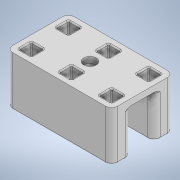
# Autodesk Inventor part: suport_culisant_new_2
Saved by Autodesk Inventor 2022.6 (Build 266554000, 554)
## iProperties
Created: 2026-01-10
Part Number: suport_culisant_new_2
Material: Generic
Document SubType Name: Modeling
Designer: Dragos Macovei
Density: 1 g/cm^3
Appearance: Default
Author: Dragos Macovei
Autodesk Inventor part; units mm, degrees
ref_plane "YZ Plane" through (0, 0, 0) normal (1, 0, 0) x (0, 1, 0)
ref_plane "XZ Plane" through (0, 0, 0) normal (0, 1, 0) x (-1, 0, 0)
ref_plane "XY Plane" through (0, 0, 0) normal (0, 0, 1) x (1, 0, 0)
sketch "Sketch1" plane through (0, 0, 0) normal (0, 1, 0) x (-1, 0, 0)
  line L0 (0, 0) -> (85, 0)
  line L1 (85, 0) -> (85, 18.3)
  line L2 (85, 18.3) -> (0, 18.3)
  line L3 (0, 18.3) -> (0, 0)
  line L4 (-13.0335, -28.6159) -> (-13.0335, -18.6159)
  line L5 (-13.0335, -18.6159) -> (-3.0335, -18.6159)
  line L6 (-3.0335, -28.6159) -> (-13.0335, -28.6159)
  line L7 (-3.0335, -18.6159) -> (-3.0335, -28.6159)
  line L8 (-45.5335, 1.3841) -> (-45.5335, 11.3841)
  line L9 (-68.0335, -18.6159) -> (-68.0335, -28.6159)
  line L10 (-68.0335, 11.3841) -> (-68.0335, 1.3841)
  line L11 (-83.0335, 16.3841) -> (-83.0335, -33.6159)
  line L12 (-78.0335, 1.3841) -> (-78.0335, 11.3841)
  line L13 (-78.0335, 11.3841) -> (-68.0335, 11.3841)
  line L14 (-68.0335, 1.3841) -> (-78.0335, 1.3841)
  line L15 (-78.0335, -18.6159) -> (-68.0335, -18.6159)
  line L16 (-68.0335, -28.6159) -> (-78.0335, -28.6159)
  line L17 (-45.5335, -28.6159) -> (-45.5335, -18.6159)
  line L18 (-78.0335, -28.6159) -> (-78.0335, -18.6159)
  line L19 (-35.5335, -18.6159) -> (-35.5335, -28.6159)
  line L20 (-3.0335, 1.3841) -> (-13.0335, 1.3841)
  line L21 (-13.0335, 1.3841) -> (-13.0335, 11.3841)
  line L22 (-3.0335, 11.3841) -> (-3.0335, 1.3841)
  line L23 (-13.0335, 11.3841) -> (-3.0335, 11.3841)
  line L24 (-45.5335, -18.6159) -> (-35.5335, -18.6159)
  line L25 (-35.5335, -28.6159) -> (-45.5335, -28.6159)
  line L26 (1.9665, -33.6159) -> (1.9665, 16.3841)
  circle A0 centre (-40.5335, -8.6159) radius 5.1064
  line L27 (-83.0335, -33.6159) -> (1.9665, -33.6159)
  line L28 (1.9665, 16.3841) -> (-83.0335, 16.3841)
  line L29 (-35.5335, 11.3841) -> (-35.5335, 1.3841)
  line L30 (-35.5335, 1.3841) -> (-45.5335, 1.3841)
  line L31 (-45.5335, 11.3841) -> (-35.5335, 11.3841)
  circle A1 centre (-40.5335, -8.6159) radius 10.1064
  line L32 (-83.0335, -33.6159) -> (1.9665, 16.3841) construction
  line L33 (1.9665, -33.6159) -> (-83.0335, 16.3841) construction
  point P0 (-40.5335, -28.6159)
  point P1 (-40.5335, 16.3841)
  point P2 (-40.5335, 11.3841)
  point P3 (-73.0335, 11.3841)
  point P4 (-8.0335, 11.3841)
  point P5 (-78.0335, -23.6159)
  point P6 (-78.0335, 6.3841)
  point P7 (-35.5335, -23.6159)
  point P8 (-35.5335, 6.3841)
  point P9 (-45.5335, 6.3841)
  point P10 (-3.0335, 6.3841)
  point P11 (-8.0335, -28.6159)
  point P12 (-3.0335, -23.6159)
  point P13 (-13.0335, -23.6159)
  point P14 (1.9665, -8.6159)
  dimension "d0" = 85
  dimension "d1" = 18.3
  dimension "d68" = 5
  dimension "d69" = 5
  dimension "d70" = 5
  dimension "d71" = 5
  dimension "d72" = 5
  dimension "d73" = 5
  dimension "d74" = 10
  dimension "d75" = 10
  dimension "d76" = 10
  dimension "d77" = 10
  dimension "d78" = 10
  dimension "d79" = 10
  dimension "d80" = 10
  dimension "d81" = 10
  dimension "d82" = 10
  dimension "d83" = 10
  dimension "d84" = 10
  dimension "d85" = 10
  dimension "d86" = 5
  dimension "d87" = 5
  dimension "d88" = 5
  dimension "d89" = 5
  dimension "d90" = 85
  dimension "d91" = 50
  dimension "d92" = 55
  dimension "d93" = 22.5
  dimension "d94" = 22.5
  dimension "d95" = 5
  dimension "d96" = 5
  constraints: 68 end point, 16 midpoint, 15 perpendicular, 2 centre point, 2 coincident, 2 parallel, 1 horizontal
  measures "d0" distance of L2.end L1.end
  measures "d1" distance of L0.end L1.end
  measures "d68" radial gap between concentric circles of A0 A1
  measures "d69" distance from line of L28 point (-8.033, 11.384)
  measures "d70" distance between parallel lines of L27 L6
  measures "d71" distance between parallel lines of L27 L16
  measures "d72" distance from line of L11 point (-78.033, -23.616)
  measures "d73" distance from line of L11 point (-78.033, 6.384)
  measures "d74" distance between parallel lines of L9 L18
  measures "d75" distance between parallel lines of L15 L16
  measures "d76" distance from line of L13 L14.end
  measures "d77" distance between parallel lines of L10 L12
  measures "d78" distance between parallel lines of L25 L24
  measures "d79" distance from line of point (-35.533, -23.616) L17
  measures "d80" distance of point (-35.533, 6.384) point (-45.533, 6.384)
  measures "d81" distance between parallel lines of L30 L31
  measures "d82" distance between parallel lines of L23 L20
  measures "d83" distance from line of point (-3.033, 6.384) L21
  measures "d84" distance from line of point (-8.033, -28.616) L5
  measures "d85" distance of point (-3.033, -23.616) point (-13.033, -23.616)
  measures "d86" distance between parallel lines of L28 L31
  measures "d87" distance between parallel lines of L27 L25
  measures "d88" distance between parallel lines of L26 L22
  measures "d89" distance between parallel lines of L26 L7
  measures "d90" distance from line of point (1.967, -8.616) L11
  measures "d91" distance between parallel lines of L28 L27
  measures "d92" distance between parallel lines of L4 L9
  measures "d93" distance between parallel lines of L9 L17
  measures "d94" distance from line of L8.end L10
  measures "d95" distance from line of L28 L10.start
  measures "d96" distance from line of L28 L13.start
extrude "Extrusion1" add sketch "Sketch1" along normal blind 5 contours L3 L28 L26 L0 | L26 L28 L3 L2 L1 L0
sketch "Sketch10" plane through (0, 5, 0) normal (0, 1, 0) x (1, 0, 0)
  line L0 (-85, 0) -> (-85, -18.3) construction
  line L1 (-85, -18.3) -> (0, -18.3) construction
  line L2 (0, -18.3) -> (0, 0) construction
  line L3 (0, 0) -> (-85, 0) construction
  line L4 (-85, -18.3) -> (0, 0) construction
  line L5 (0, -18.3) -> (0, 0) construction
  line L6 (0, -18.3) -> (-85, 0) construction
  circle A0 centre (-42.5, -9.15) radius 5.05
  dimension "d104" = 10.1
  constraints: 4 end point, 1 centre point, 1 midpoint
  measures "d104" diameter of A0
extrude "Extrusion7" cut sketch "Sketch10" against normal through all
sketch "Sketch11" plane through (0, 5, 0) normal (0, 1, 0) x (1, 0, 0)
  line L0 (-15, -29.15) -> (-15, -19.15)
  line L1 (-15, -19.15) -> (-5, -19.15)
  line L2 (-5, -29.15) -> (-15, -29.15)
  line L3 (-5, -19.15) -> (-5, -29.15)
  line L4 (-47.5, 0.85) -> (-47.5, 10.85)
  line L5 (-70, -19.15) -> (-70, -29.15)
  line L6 (-70, 10.85) -> (-70, 0.85)
  line L7 (-85, 15.85) -> (-85, -34.15)
  line L8 (-80, 0.85) -> (-80, 10.85)
  line L9 (-80, 10.85) -> (-70, 10.85)
  line L10 (-70, 0.85) -> (-80, 0.85)
  line L11 (-80, -19.15) -> (-70, -19.15)
  line L12 (-70, -29.15) -> (-80, -29.15)
  line L13 (-47.5, -29.15) -> (-47.5, -19.15)
  line L14 (-80, -29.15) -> (-80, -19.15)
  line L15 (-37.5, -19.15) -> (-37.5, -29.15)
  line L16 (-5, 0.85) -> (-15, 0.85)
  line L17 (-15, 0.85) -> (-15, 10.85)
  line L18 (-5, 10.85) -> (-5, 0.85)
  line L19 (-15, 10.85) -> (-5, 10.85)
  line L20 (-47.5, -19.15) -> (-37.5, -19.15)
  line L21 (-37.5, -29.15) -> (-47.5, -29.15)
  line L22 (0, -34.15) -> (0, 15.85)
  line L23 (-85, -34.15) -> (0, -34.15)
  line L24 (0, 15.85) -> (-85, 15.85)
  line L25 (-37.5, 10.85) -> (-37.5, 0.85)
  line L26 (-37.5, 0.85) -> (-47.5, 0.85)
  line L27 (-47.5, 10.85) -> (-37.5, 10.85)
  circle A0 centre (-42.5, -9.15) radius 10.1064
  line L28 (-85, -34.15) -> (0, 15.85) construction
  line L29 (0, -34.15) -> (-85, 15.85) construction
  circle A1 centre (-42.5, -9.15) radius 5.05 projected
  line L30 (-85, 0) -> (-85, -18.3) projected
  line L31 (-85, -18.3) -> (0, -18.3) projected
  line L32 (0, -18.3) -> (0, 0) projected
  line L33 (0, 0) -> (-85, 0) projected
  line L34 (0, 0) -> (-85, 0) projected
  point P0 (-42.5, -29.15)
  point P1 (-42.5, 15.85)
  point P2 (-42.5, 10.85)
  point P3 (-75, 10.85)
  point P4 (-10, 10.85)
  point P5 (-80, -24.15)
  point P6 (-80, 5.85)
  point P7 (-37.5, -24.15)
  point P8 (-37.5, 5.85)
  point P9 (-47.5, 5.85)
  point P10 (-5, 5.85)
  point P11 (-10, -29.15)
  point P12 (-5, -24.15)
  point P13 (-15, -24.15)
  point P14 (0, -9.15)
  dimension "d108" = 5
  dimension "d109" = 5
  dimension "d110" = 5
  dimension "d111" = 5
  dimension "d112" = 5
  dimension "d113" = 10
  dimension "d114" = 10
  dimension "d115" = 10
  dimension "d116" = 10
  dimension "d117" = 10
  dimension "d118" = 10
  dimension "d119" = 10
  dimension "d120" = 10
  dimension "d121" = 10
  dimension "d122" = 10
  dimension "d123" = 10
  dimension "d124" = 10
  dimension "d125" = 5
  dimension "d126" = 5
  dimension "d127" = 5
  dimension "d128" = 5
  dimension "d129" = 85
  dimension "d130" = 50
  dimension "d131" = 55
  dimension "d132" = 22.5
  dimension "d133" = 22.5
  dimension "d134" = 5
  dimension "d135" = 5
  constraints: 60 end point, 17 midpoint, 16 perpendicular, 1 centre point, 1 coincident
  measures "d108" distance from line of L24 point (-10, 10.85)
  measures "d109" distance between parallel lines of L23 L2
  measures "d110" distance between parallel lines of L23 L12
  measures "d111" distance from line of L7 point (-80, -24.15)
  measures "d112" distance from line of L7 point (-80, 5.85)
  measures "d113" distance between parallel lines of L5 L14
  measures "d114" distance between parallel lines of L11 L12
  measures "d115" distance from line of L9 L8.start
  measures "d116" distance between parallel lines of L6 L8
  measures "d117" distance between parallel lines of L21 L20
  measures "d118" distance from line of point (-37.5, -24.15) L13
  measures "d119" distance of point (-37.5, 5.85) point (-47.5, 5.85)
  measures "d120" distance between parallel lines of L26 L27
  measures "d121" distance between parallel lines of L19 L16
  measures "d122" distance from line of point (-5, 5.85) L17
  measures "d123" distance from line of point (-10, -29.15) L1
  measures "d124" distance of point (-5, -24.15) point (-15, -24.15)
  measures "d125" distance between parallel lines of L24 L27
  measures "d126" distance between parallel lines of L23 L21
  measures "d127" distance between parallel lines of L22 L18
  measures "d128" distance between parallel lines of L22 L3
  measures "d129" distance from line of point (0, -9.15) L7
  measures "d130" distance between parallel lines of L24 L23
  measures "d131" distance between parallel lines of L0 L5
  measures "d132" distance between parallel lines of L5 L13
  measures "d133" distance from line of L4.end L6
  measures "d134" distance from line of L24 L6.start
  measures "d135" distance from line of L24 L8.end
extrude "Extrusion8" add sketch "Sketch11" against normal blind 40 contours L26 A0 L33 L7 L24 L22 L25 L27 L4 | L26 A0 L33 | L31 A0 L20 | A0 L20 L13 L21 L15 L31 L22 L23 L7
fillet "Fillet1" radius 1 24 edges at (-15, -15, 19.15) (-15, -15, 29.15) (-47.5, -15, 29.15) (-47.5, -15, 19.15) (-47.5, -15, -10.85) (-47.5, -15, -0.85) (-15, -15, -0.85) (-15, -15, -10.85) (-80, -15, -10.85) (-80, -15, -0.85) (-80, -15, 19.15) (-80, -15, 29.15) (-70, -15, 19.15) (-70, -15, -10.85) (-37.5, -15, -10.85) (-37.5, -15, 19.15) (-5, -15, -10.85) (-5, -15, 19.15) (-5, -15, 29.15) (-5, -15, -0.85) (-37.5, -15, -0.85) (-37.5, -15, 29.15) (-70, -15, 29.15) (-70, -15, -0.85)
fillet "Fillet2" radius 1 24 edges at (-75, 5, 29.15) (-80, 5, 24.15) (-75, 5, 19.15) (-70, 5, 24.15) (-75, 5, -0.85) (-80, 5, -5.85) (-75, 5, -10.85) (-70, 5, -5.85) (-42.5, 5, 19.15) (-37.5, 5, 24.15) (-42.5, 5, 29.15) (-47.5, 5, 24.15) (-42.5, 5, -0.85) (-37.5, 5, -5.85) (-42.5, 5, -10.85) (-47.5, 5, -5.85) (-10, 5, 19.15) (-5, 5, 24.15) (-10, 5, 29.15) (-15, 5, 24.15) (-10, 5, -10.85) (-5, 5, -5.85) (-10, 5, -0.85) (-15, 5, -5.85)
fillet "Fillet3" radius 5 4 edges at (0, -15, -15.85) (0, -15, 34.15) (-85, -15, -15.85) (-85, -15, 34.15)
fillet "Fillet4" radius 5 4 edges at (-85, -17.5, 18.3) (-85, -17.5, 0) (0, -17.5, 18.3) (0, -17.5, 0)
fillet "Fillet5" radius 1 16 edges at (-1.4645, -35, 19.7645) (0, -35, 26.225) (0, -35, -7.925) (-1.4645, -35, 32.6855) (-42.5, -35, 34.15) (-83.5355, -35, 32.6855) (-85, -35, 26.225) (-85, -35, -7.925) (-83.5355, -35, 19.7645) (-42.5, -35, 18.3) (-83.5355, -35, -1.4645) (-83.5355, -35, -14.3855) (-42.5, -35, -15.85) (-1.4645, -35, -14.3855) (-1.4645, -35, -1.4645) (-42.5, -35, 0)
fillet "Fillet6" radius 2 2 edges at (-42.5, 0, 0) (-42.5, 0, 18.3)
equation "\"d69\" = d97"
equation "\"d70\" = d98"
equation "\"d71\" = d98"
equation "\"d73\" = d72"
equation "\"d74\" = d99"
equation "\"d75\" = d74"
equation "\"d76\" = d75"
equation "\"d77\" = d75"
equation "\"d78\" = d75"
equation "\"d79\" = d74"
equation "\"d80\" = d79"
equation "\"d81\" = d80"
equation "\"d82\" = d80"
equation "\"d83\" = d80"
equation "\"d84\" = d82"
equation "\"d85\" = d82"
equation "\"d86\" = d100"
equation "\"d87\" = d71"
equation "\"d88\" = d89"
equation "\"d89\" = d100"
equation "\"d93\" = -0.5 * d79 + 0.5 * d92"
equation "\"d94\" = d93"
equation "\"d95\" = d71"
equation "\"d108\" = d136"
equation "\"d109\" = d137"
equation "\"d110\" = d137"
equation "\"d112\" = d111"
equation "\"d113\" = d138"
equation "\"d114\" = d113"
equation "\"d115\" = d114"
equation "\"d116\" = d114"
equation "\"d117\" = d114"
equation "\"d118\" = d113"
equation "\"d119\" = d118"
equation "\"d120\" = d119"
equation "\"d121\" = d119"
equation "\"d122\" = d119"
equation "\"d123\" = d121"
equation "\"d124\" = d121"
equation "\"d125\" = d139"
equation "\"d126\" = d110"
equation "\"d127\" = d128"
equation "\"d128\" = d139"
equation "\"d132\" = -0.5 * d118 + 0.5 * d131"
equation "\"d133\" = d132"
equation "\"d134\" = d110"
equation "\"d100\" = d97"
equation "\"d139\" = d136"
equation "\"d98\" = 5"
equation "\"d99\" = 10"
equation "\"d137\" = 5"
equation "\"d138\" = 10"
equation "\"d97\" = 5"
equation "\"d136\" = 5"
body "Solid1"
